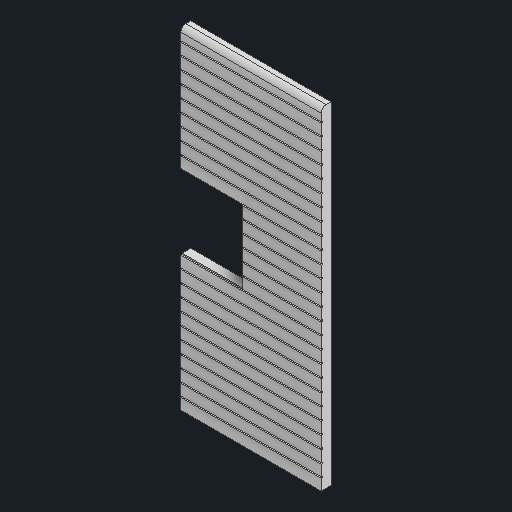
# Autodesk Inventor part: 7_1_3_vollet_cote_milieu
Saved by Autodesk Inventor 2026 (Build 300175000, 175)
## iProperties
Created: 2025-06-21
Part Number: 7_1_3_vollet_cote_milieu
Material: Generic
Document SubType Name: Modeling
Designer: remg9
Density: 1 g/cm^3
Appearance: Default
Author: remg9
Autodesk Inventor part; units mm, degrees
ref_plane "YZ Plane" through (0, 0, 0) normal (1, 0, 0) x (0, 1, 0)
ref_plane "XZ Plane" through (0, 0, 0) normal (0, 1, 0) x (-1, 0, 0)
ref_plane "XY Plane" through (0, 0, 0) normal (0, 0, 1) x (1, 0, 0)
sketch "Sketch1" plane through (0, 0, 0) normal (0, 0, 1) x (1, 0, 0)
  line L0 (0, 0) -> (57, 0)
  line L1 (57, 0) -> (57, 135)
  line L2 (57, 135) -> (0, 135)
  line L3 (0, 135) -> (0, 0)
  dimension "d0" = 135
  dimension "d1" = 57
  constraints: 8 end point, 2 parallel, 1 horizontal, 1 perpendicular
  measures "d0" distance of L0.end L1.end
  measures "d1" distance of L1.end L2.end
extrude "Extrusion1" add sketch "Sketch1" along normal blind 4
sketch "Sketch2" plane through (0, 0, 4) normal (0, 0, 1) x (1, 0, 0)
  line L0 (0, 130) -> (57, 130)
  line L1 (57, 130) -> (57, 129.5)
  line L2 (57, 129.5) -> (0, 129.5)
  line L3 (0, 129.5) -> (0, 130)
  line L4 (0, 135) -> (0, 0) projected
  line L5 (57, 0) -> (57, 135) projected
  line L6 (57, 135) -> (0, 135) projected
  line L7 (0, 125) -> (57, 125)
  line L8 (57, 125) -> (57, 124.5)
  line L9 (57, 124.5) -> (0, 124.5)
  line L10 (0, 124.5) -> (0, 125)
  line L11 (0, 120) -> (57, 120)
  line L12 (57, 120) -> (57, 119.5)
  line L13 (57, 119.5) -> (0, 119.5)
  line L14 (0, 119.5) -> (0, 120)
  line L15 (0, 115) -> (57, 115)
  line L16 (57, 115) -> (57, 114.5)
  line L17 (57, 114.5) -> (0, 114.5)
  line L18 (0, 114.5) -> (0, 115)
  line L19 (0, 110) -> (57, 110)
  line L20 (57, 110) -> (57, 109.5)
  line L21 (57, 109.5) -> (0, 109.5)
  line L22 (0, 109.5) -> (0, 110)
  line L23 (0, 105) -> (57, 105)
  line L24 (57, 105) -> (57, 104.5)
  line L25 (57, 104.5) -> (0, 104.5)
  line L26 (0, 104.5) -> (0, 105)
  line L27 (0, 100) -> (57, 100)
  line L28 (57, 100) -> (57, 99.5)
  line L29 (57, 99.5) -> (0, 99.5)
  line L30 (0, 99.5) -> (0, 100)
  line L31 (0, 95) -> (57, 95)
  line L32 (57, 95) -> (57, 94.5)
  line L33 (57, 94.5) -> (0, 94.5)
  line L34 (0, 94.5) -> (0, 95)
  line L35 (0, 90) -> (57, 90)
  line L36 (57, 90) -> (57, 89.5)
  line L37 (57, 89.5) -> (0, 89.5)
  line L38 (0, 89.5) -> (0, 90)
  line L39 (0, 85) -> (57, 85)
  line L40 (57, 85) -> (57, 84.5)
  line L41 (57, 84.5) -> (0, 84.5)
  line L42 (0, 84.5) -> (0, 85)
  line L43 (0, 80) -> (57, 80)
  line L44 (57, 80) -> (57, 79.5)
  line L45 (57, 79.5) -> (0, 79.5)
  line L46 (0, 79.5) -> (0, 80)
  line L47 (0, 75) -> (57, 75)
  line L48 (57, 75) -> (57, 74.5)
  line L49 (57, 74.5) -> (0, 74.5)
  line L50 (0, 74.5) -> (0, 75)
  line L51 (0, 70) -> (57, 70)
  line L52 (57, 70) -> (57, 69.5)
  line L53 (57, 69.5) -> (0, 69.5)
  line L54 (0, 69.5) -> (0, 70)
  line L55 (0, 65) -> (57, 65)
  line L56 (57, 65) -> (57, 64.5)
  line L57 (57, 64.5) -> (0, 64.5)
  line L58 (0, 64.5) -> (0, 65)
  line L59 (0, 60) -> (57, 60)
  line L60 (57, 60) -> (57, 59.5)
  line L61 (57, 59.5) -> (0, 59.5)
  line L62 (0, 59.5) -> (0, 60)
  line L63 (0, 55) -> (57, 55)
  line L64 (57, 55) -> (57, 54.5)
  line L65 (57, 54.5) -> (0, 54.5)
  line L66 (0, 54.5) -> (0, 55)
  line L67 (0, 50) -> (57, 50)
  line L68 (57, 50) -> (57, 49.5)
  line L69 (57, 49.5) -> (0, 49.5)
  line L70 (0, 49.5) -> (0, 50)
  line L71 (0, 45) -> (57, 45)
  line L72 (57, 45) -> (57, 44.5)
  line L73 (57, 44.5) -> (0, 44.5)
  line L74 (0, 44.5) -> (0, 45)
  line L75 (0, 40) -> (57, 40)
  line L76 (57, 40) -> (57, 39.5)
  line L77 (57, 39.5) -> (0, 39.5)
  line L78 (0, 39.5) -> (0, 40)
  line L79 (0, 35) -> (57, 35)
  line L80 (57, 35) -> (57, 34.5)
  line L81 (57, 34.5) -> (0, 34.5)
  line L82 (0, 34.5) -> (0, 35)
  line L83 (0, 30) -> (57, 30)
  line L84 (57, 30) -> (57, 29.5)
  line L85 (57, 29.5) -> (0, 29.5)
  line L86 (0, 29.5) -> (0, 30)
  line L87 (0, 25) -> (57, 25)
  line L88 (57, 25) -> (57, 24.5)
  line L89 (57, 24.5) -> (0, 24.5)
  line L90 (0, 24.5) -> (0, 25)
  line L91 (0, 20) -> (57, 20)
  line L92 (57, 20) -> (57, 19.5)
  line L93 (57, 19.5) -> (0, 19.5)
  line L94 (0, 19.5) -> (0, 20)
  line L95 (0, 15) -> (57, 15)
  line L96 (57, 15) -> (57, 14.5)
  line L97 (57, 14.5) -> (0, 14.5)
  line L98 (0, 14.5) -> (0, 15)
  line L99 (0, 10) -> (57, 10)
  line L100 (57, 10) -> (57, 9.5)
  line L101 (57, 9.5) -> (0, 9.5)
  line L102 (0, 9.5) -> (0, 10)
  line L103 (0, 5) -> (57, 5)
  line L104 (57, 5) -> (57, 4.5)
  line L105 (57, 4.5) -> (0, 4.5)
  line L106 (0, 4.5) -> (0, 5)
  point P0 (57, 4.5)
  point P1 (57, 5)
  point P2 (57, 9.5)
  point P3 (57, 10)
  point P4 (57, 14.5)
  point P5 (57, 15)
  point P6 (57, 19.5)
  point P7 (57, 20)
  point P8 (57, 24.5)
  point P9 (57, 25)
  point P10 (57, 29.5)
  point P11 (57, 30)
  point P12 (57, 34.5)
  point P13 (57, 35)
  point P14 (57, 39.5)
  point P15 (57, 40)
  point P16 (57, 44.5)
  point P17 (57, 45)
  point P18 (57, 49.5)
  point P19 (57, 50)
  point P20 (57, 54.5)
  point P21 (57, 55)
  point P22 (57, 59.5)
  point P23 (57, 60)
  point P24 (57, 64.5)
  point P25 (57, 65)
  point P26 (57, 69.5)
  point P27 (57, 74.5)
  point P28 (57, 79.5)
  point P29 (57, 84.5)
  point P30 (57, 89.5)
  point P31 (57, 94.5)
  point P32 (57, 99.5)
  point P33 (57, 125)
  dimension "d4" = 0.5
  dimension "d5" = 5
  dimension "d8" = 5
  constraints: 208 end point, 100 vertical alignment, 52 parallel, 50 collinear, 2 vertical, 1 horizontal, 1 perpendicular, 2 other
  measures "d4" distance between parallel lines of L2 L0
  measures "d5" distance between parallel lines of L6 L0
  measures "d8" distance of L0.start L7.start
extrude "Extrusion2" cut sketch "Sketch2" against normal blind 0.5 contours L0 L1 L2 L3 | L7 L5 L9 L4 | L11 L5 L13 L4 | L15 L5 L17 L4 | L19 L5 L21 L4 | L23 L5 L25 L4 | L27 L5 L29 L4 | L31 L5 L33 L4 | L35 L5 L37 L4 | L39 L5 L41 L4 | L43 L5 L45 L4 | L47 L5 L49 L4 | L51 L5 L53 L4 | L55 L5 L57 L4 | L59 L5 L61 L4 | L63 L5 L65 L4 | L67 L5 L69 L4 | L71 L5 L73 L4 | L75 L5 L77 L4 | L79 L5 L81 L4 | L83 L5 L85 L4 | L87 L5 L89 L4 | L91 L5 L93 L4 | L95 L5 L97 L4 | L99 L5 L101 L4 | L103 L5 L105 L4
fillet "Fillet1" radius 2 1 edges at (28.5, 135, 4)
sketch "Sketch3" plane through (0, 0, 4) normal (0, 0, 1) x (1, 0, 0)
  line L0 (0, 84.5) -> (25, 84.5)
  line L1 (25, 84.5) -> (25, 55)
  line L2 (25, 55) -> (0, 55)
  line L3 (0, 55) -> (0, 84.5)
  line L4 (57, 84.5) -> (0, 84.5) projected
  line L5 (0, 84.5) -> (0, 80) projected
  line L6 (0, 55) -> (57, 55) projected
  point P0 (0, 0)
  dimension "d16" = 25
  constraints: 8 end point, 3 collinear, 2 parallel, 1 horizontal, 1 perpendicular
  measures "d16" distance between parallel lines of L1 L3
extrude "Extrusion3" cut sketch "Sketch3" against normal blind 10
body "Solid1"
